calibrateur_robot_v5 (Autodesk Fusion 360 design; units mm, degrees)
Autodesk Fusion 360 part; units mm, degrees
sketch "Sketch1" plane through (0, 0, 0) normal (0, 1, 0) x (1, 0, 0)
  line L0 (0, 0) -> (30, 0)
  line L1 (30, 0) -> (30, -100.4)
  line L2 (30, -100.4) -> (0, -100.4)
  line L3 (0, -100.4) -> (0, 0)
  line L4 (0, -100.4) -> (30, -100.4)
  line L5 (30, -100.4) -> (30, -105.4)
  line L6 (30, -105.4) -> (0, -105.4)
  line L7 (0, -105.4) -> (0, -100.4)
  line L8 (0, 0) -> (30, 0)
  line L9 (30, 0) -> (30, 5)
  line L10 (30, 5) -> (0, 5)
  line L11 (0, 5) -> (0, 0)
  line L12 (0, 5) -> (30, 5)
  line L13 (30, 5) -> (30, 25)
  line L14 (30, 25) -> (0, 25)
  line L15 (0, 25) -> (0, 5)
  line L16 (30, 25) -> (25, 25)
  line L17 (25, 25) -> (25, -105.4)
  line L18 (25, -105.4) -> (30, -105.4)
  line L19 (30, -105.4) -> (30, 25)
  line L20 (0, -100.4) -> (25, -100.4)
  line L21 (25, -100.4) -> (25, -98.4)
  line L22 (25, -98.4) -> (0, -98.4)
  line L23 (0, -98.4) -> (0, -100.4)
  dimension "d1" = 30
  dimension "d2" = 100.4
  dimension "d3" = 5
  dimension "d4" = 5
  dimension "d5" = 20
  dimension "d18" = 5
  dimension "d30" = 2
  constraint horizontal L0
  constraint vertical L1
  constraint horizontal L2
  constraint vertical L3
  constraint coincident L0.start L3.end
  constraint horizontal L4
  constraint vertical L5
  constraint horizontal L6
  constraint vertical L7
  constraint horizontal L8
  constraint vertical L9
  constraint horizontal L10
  constraint vertical L11
  constraint horizontal L12
  constraint vertical L13
  constraint horizontal L14
  constraint vertical L15
  constraint horizontal L16
  constraint vertical L17
  constraint horizontal L18
  constraint vertical L19
  constraint coincident L6 L17.end
  constraint horizontal L20
  constraint vertical L21
  constraint horizontal L22
  constraint vertical L23
  measures "d1" distance of L0.start L0.end
  measures "d2" distance of L0.start L2.end
  measures "d3" distance of L2.end L6.end
  measures "d4" distance of L0.start L10.end
  measures "d5" distance of L10.end L14.end
  measures "d18" distance of L13.end L16.end
  measures "d30" distance of L2.end L22.end
extrude "Extrude1" add sketch "Sketch1" against normal blind 5
extrude "Extrude2" add sketch "Sketch1" along normal blind 15 contours L0 L8 L10 L11 L12 L17 | L0 L8 L9 L10 L12 L17 L19 | L2 L4 L6 L7 L17 L20 | L2 L4 L5 L6 L17 L18 L19
fillet "Fillet1" radius 17.5 1 edges at (15, 0, -5)
extrude "Extrude3" add sketch "Sketch1" against normal blind 30 contours L0 L8 L9 L10 L12 L17 L19 | L0 L1 L2 L4 L8 L17 L19 L21 | L10 L12 L13 L14 L16 L17 L19 | L2 L4 L5 L6 L17 L18 L19
fillet "Fillet5" radius 20 1 edges at (0, -2.5, -25)
extrude "Extrude4" add sketch "Sketch1" against normal blind 30 contours L2 L3 L4 L17 L20 L21 L22 L23
extrude "Extrude5" add 1 faces at (16.6667, -13.3333, 100.4) along direction (0, 0, 1) blind 5
chamfer "Chamfer1" distance 25 angle 45 1 edges at (0, -30, 101.9) tangent chain off
fillet "Fillet6" radius 7 2 edges at (27.5, -30, 105.4) (27.5, -30, -25)
fillet "Fillet7" radius 11 1 edges at (12.5, -5, 98.4)
